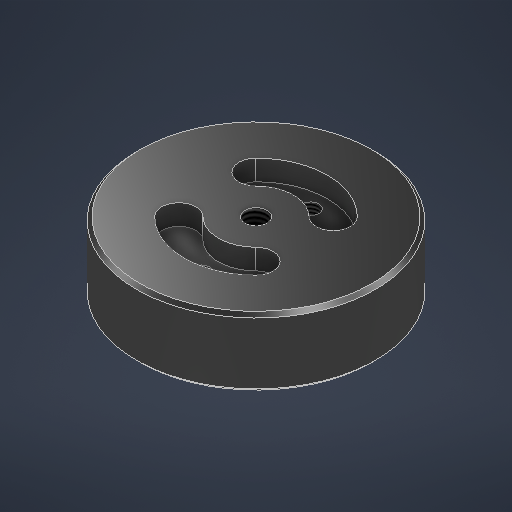
# Autodesk Inventor part: Port Block
Saved by Autodesk Inventor 2026.3 (Build 303398000, 398)
## iProperties
Created: 2026-11-02
Part Number: Port Block
Material: Steel
Document SubType Name: Modeling
Designer: ADMIN
Density: 7.85 g/cm^3
Appearance: Glossy - Black
Author: ADMIN
Autodesk Inventor part; units mm, degrees
ref_plane "YZ Plane" through (0, 0, 0) normal (1, 0, 0) x (0, 1, 0)
ref_plane "XZ Plane" through (0, 0, 0) normal (0, 1, 0) x (-1, 0, 0)
ref_plane "XY Plane" through (0, 0, 0) normal (0, 0, 1) x (1, 0, 0)
sketch "Sketch1" plane through (0, 0, 0) normal (0, 1, 0) x (-1, 0, 0)
  circle A0 centre (0, 0) radius 17.5
  dimension "d0" = 35
  constraints: 1 centre point, 1 coincident
  measures "d0" diameter of A0
extrude "Extrusion1" add sketch "Sketch1" along normal mid plane 10
sketch "Sketch2" plane through (0, 5, 0) normal (0, 1, 0) x (1, 0, 0)
  point P0 (0, 0)
  point P1 (0, 0)
  constraints: 1 coincident
hole "Hole1" at (0, 5, 0) direction (0, -1, 0) diameter 3.242 end through all thread size "M4x0.7" class "6H" standard "ANSI Metric M Profile"
sketch "Sketch3" plane through (0, 5, 0) normal (0, 1, 0) x (1, 0, 0)
  circle A0 centre (0, 0) radius 8 construction
  line L0 (0, 0) -> (5.6569, 5.6569) construction
  circle A1 centre (0, 0) radius 17.5 projected
  line L1 (-17.5, 0) -> (17.5, 0) construction
  arc A2 (3.8891, 3.8891) -> (7.4246, 7.4246) centre (5.6569, 5.6569) ccw
  line L2 (0, 0) -> (-5.6569, 5.6569) construction
  arc A3 (-7.4246, 7.4246) -> (-3.8891, 3.8891) centre (-5.6569, 5.6569) ccw
  arc A4 (7.4246, 7.4246) -> (-7.4246, 7.4246) centre (0, 0) ccw
  arc A5 (3.8891, 3.8891) -> (-3.8891, 3.8891) centre (0, 0) ccw
  dimension "d11" = 16
  dimension "d12" = 45
  dimension "d14" = 5
  dimension "d16" = 45
  dimension "d17" = 5
  constraints: 12 point on circle, 6 end point, 5 centre point, 5 coincident, 2 tangent, 1 horizontal, 1 midpoint
  measures "d11" diameter of A0
  measures "d12" angle of L1 L0
  measures "d14" diameter of A2
  measures "d16" angle of L1 L2
  measures "d17" diameter of A3
extrude "Extrusion2" cut sketch "Sketch3" against normal blind 3 contours A5 A3 A4 A2
mirror "Mirror1" about plane through (0, 0, 0) normal (0, 0, 1) of "Extrusion2"
sketch "Sketch4" plane through (0, 2, 0) normal (0, 1, 0) x (1, 0, 0)
  point P0 (0, 0)
  point P1 (0, 8)
  dimension "d22" = 8
  constraints: 1 vertical alignment
  measures "d22" distance of point (0, 0) point (0, 8)
hole "Hole2" at (0, 2, -8) direction (0, -1, 0) diameter 2.459 end through all thread size "M3x0.5" class "6H" standard "ANSI Metric M Profile"
mirror "Mirror2" about plane through (0, 0, 0) normal (0, 0, 1) of "Hole2"
sketch "Sketch5" plane through (0, -5, 0) normal (0, -1, 0) x (1, 0, 0)
  point P0 (0, 0)
  point P1 (-12.5, 0)
  point P2 (12.5, 0)
  dimension "d30" = 12.5
  dimension "d31" = 12.5
  constraints: 2 horizontal alignment
  measures "d30" distance of point (0, 0) point (-12.5, 0)
  measures "d31" distance of point (0, 0) point (12.5, 0)
hole "Hole3" at (-12.5, -5, 0) at (12.5, -5, 0) direction (0, 1, 0) diameter 3.242 depth 8 thread size "M4x0.7" class "6H" standard "ANSI Metric M Profile"
chamfer "Chamfer1" distance 0.5 angle 45 2 edges at (17.5, 5, 0) (17.5, -5, 0)
body "Solid1"
